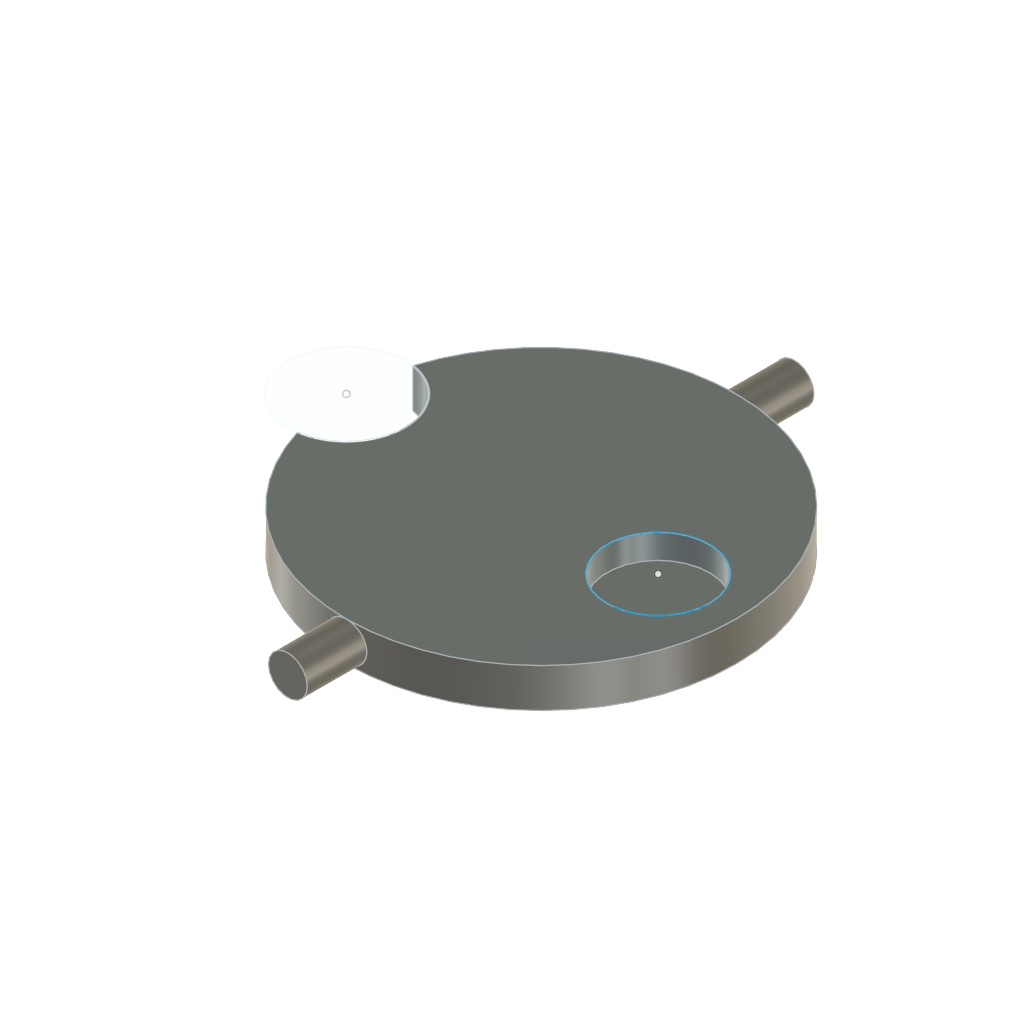
coin_dot_v1 (Autodesk Fusion 360 design; units mm, degrees)
Autodesk Fusion 360 part; units mm, degrees
sketch " MainBody" plane through (0, 0, 0) normal (0, 0, 1) x (1, 0, 0)
  circle A0 centre (0, 0) radius 10
  dimension "d1" = 20
  constraint coincident A0.centre origin
  measures "d1" diameter of A0
extrude "Extrude1" add sketch " MainBody" along normal blind 2 makes body 1
sketch "Posts" plane through (0, 0, 0) normal (0, 1, 0) x (1, 0, 0)
  circle A0 centre (0, -1) radius 1
  dimension "d5" = 2
  measures "d5" diameter of A0
extrude "Extrude2" add sketch "Posts" along normal blind 13 and the other way blind 13 separate body makes body 2
combine "Combine1" operation add target body 1 tool bodies 2
sketch "Sketch10" plane through (0, 0, 2) normal (0, 0, 1) x (-1, 0, 0)
  arc A0 (0, -10) -> (0, 10) centre (0, 0) ccw
  arc A1 (0, 10) -> (0, -10) centre (0, 0) ccw
  circle A2 centre (-6, 0) radius 2.625
  circle A3 centre (10, 0) radius 3
  dimension "d25" = 5.25
  dimension "d32" = 6
  constraint midpoint A0 A3.centre
  measures "d25" diameter of A2
  measures "d32" diameter of A3
extrude "Extrude8" cut sketch "Sketch10" against normal blind 1.25 contours A2 bodies 1
extrude "Extrude9" cut sketch "Sketch10" against normal blind 2 contours A0 A3 picked at (8.9907, 0.0747) bodies 1
